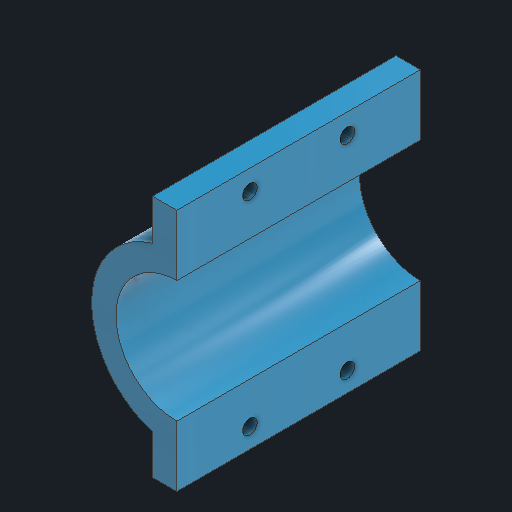
# Autodesk Inventor part: suporte_caneta
Saved by Autodesk Inventor 2026 (Build 300175000, 175)
## iProperties
Created: 2025-04-25
Part Number: suporte_caneta
Material: Genérico
Document SubType Name: Modeling
Designer: MARIA
Density: 1 g/cm^3
Appearance: Padrão
Author: MARIA
Autodesk Inventor part; units mm, degrees
ref_plane "YZ Plane" through (0, 0, 0) normal (1, 0, 0) x (0, 1, 0)
ref_plane "XZ Plane" through (0, 0, 0) normal (0, 1, 0) x (-1, 0, 0)
ref_plane "XY Plane" through (0, 0, 0) normal (0, 0, 1) x (1, 0, 0)
sketch "Esboço2" plane through (0, 0, 0) normal (0, 0, 1) x (1, 0, 0)
  line L0 (36.6523, 86.2699) -> (36.6523, 73.7699)
  arc A0 (36.6523, 73.7699) -> (36.6523, 48.7699) centre (36.6523, 61.2699) ccw
  line L1 (36.6523, 48.7699) -> (36.6523, 36.2699)
  line L2 (36.6523, 36.2699) -> (31.6523, 36.2699)
  line L3 (31.6523, 36.2699) -> (31.6523, 44.3769)
  arc A1 (31.6523, 77.9179) -> (31.6523, 44.3769) centre (36.6523, 61.1474) ccw
  line L4 (31.6523, 77.9179) -> (31.6523, 86.2699)
  line L5 (31.6523, 86.2699) -> (36.6523, 86.2699)
  point P0 (0, 0)
  point P1 (36.6523, 80.0199)
  dimension "d6" = 0
  dimension "d7" = 5
  dimension "d8" = 12.5
  dimension "d9" = 17.5
  dimension "d10" = 12.5
  dimension "d31" = 0
  dimension "d32" = 0
  constraints: 12 end point, 4 point on circle, 4 vertical, 2 centre point, 2 equal length, 2 perpendicular, 1 midpoint
  measures "d6" horizontal distance of A1.centre A0.centre
  measures "d7" distance between parallel lines of L0 L4
  measures "d8" radius of A0
  measures "d9" radius of A1
  measures "d10" distance of L0.start L0.end
  measures "d31" distance from line of L0 A0.centre
  measures "d32" distance from line of point (36.652, 80.02) L1
extrude "Extrusão2" add sketch "Esboço2" along normal blind 50
sketch "Esboço3" plane through (31.6523, 77.9179, 0) normal (-1, 0, 0) x (0, 0, 1)
  circle A0 centre (15, 4.176) radius 1.5
  circle A1 centre (35, 4.176) radius 1.5
  line L0 (0, 8.352) -> (50, 8.352) projected
  line L1 (0, 0) -> (50, 0) projected
  line L2 (50, 8.352) -> (50, 0) projected
  line L3 (0, 8.352) -> (0, 0) projected
  point P0 (0, -77.9179)
  dimension "d15" = 3
  dimension "d16" = 4.176
  dimension "d17" = 8.352
  dimension "d18" = 15
  dimension "d19" = 15
  dimension "d20" = 4.176
  constraints: 2 centre point, 1 equal radius
  measures "d15" diameter of A0
  measures "d16" distance from line of L0 A1.centre
  measures "d17" distance between parallel lines of L1 L0
  measures "d18" distance from line of L2 A1.centre
  measures "d19" distance from line of L3 A0.centre
  measures "d20" distance from line of L0 A0.centre
extrude "Extrusão3" cut sketch "Esboço3" against normal through all contours A0 | A1
sketch "Esboço4" plane through (31.6523, 36.2699, 0) normal (-1, 0, 0) x (0, 0, 1)
  circle A0 centre (15, 4.0535) radius 1.5
  circle A1 centre (35, 4.0535) radius 1.5
  line L0 (0, 8.107) -> (0, 0) projected
  line L1 (0, 0) -> (50, 0) projected
  line L2 (0, 8.107) -> (50, 8.107) projected
  line L3 (50, 8.107) -> (50, 0) projected
  point P0 (0, -36.2699)
  dimension "d23" = 3
  dimension "d24" = 15
  dimension "d25" = 4.0535
  dimension "d26" = 8.107
  dimension "d27" = 15
  dimension "d28" = 4.0535
  constraints: 2 centre point, 1 equal radius
  measures "d23" diameter of A0
  measures "d24" distance from line of L0 A0.centre
  measures "d25" distance from line of L1 A0.centre
  measures "d26" distance between parallel lines of L1 L2
  measures "d27" distance from line of L3 A1.centre
  measures "d28" distance from line of L1 A1.centre
extrude "Extrusão4" cut sketch "Esboço4" against normal through all contours A0 | A1
equation "\"d16\" = 0.5 * d17"
equation "\"d20\" = 0.5 * d17"
equation "\"d25\" = 0.5 * d26"
equation "\"d28\" = 0.5 * d26"
